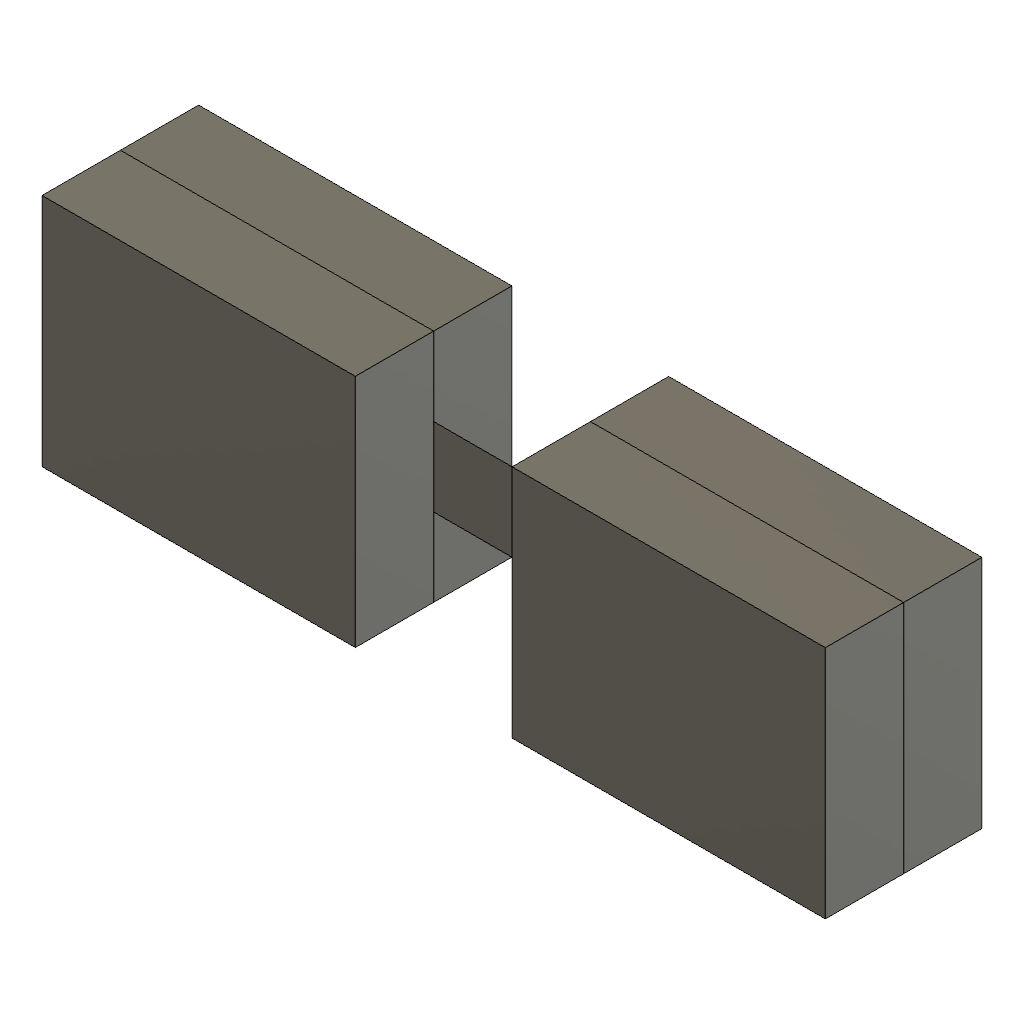
small_sheet_face_extend (Autodesk Fusion 360 design; units mm, degrees)
part number: 2026-10-21-16-23-59-782
Autodesk Fusion 360 part; units mm, degrees
sketch "OwnedMultiSplitBlockSketch_0_small_sheet_face_extend" plane through (0, 0, 0) normal (0, 0, 1) x (1, 0, 0)
  line L0 (0, 0) -> (40, 0)
  line L1 (40, 0) -> (40, 30)
  line L2 (40, 30) -> (0, 30)
  line L3 (0, 30) -> (0, 0)
extrude "OwnedMultiSplitBlockExtrude_0_small_sheet_face_extend" add sketch "OwnedMultiSplitBlockSketch_0_small_sheet_face_extend" along normal blind 20 makes body 1
sketch "OwnedMultiSplitBlockSketch_1_small_sheet_face_extend" plane through (0, 0, 0) normal (0, 0, 1) x (1, 0, 0)
  line L0 (60, 0) -> (100, 0)
  line L1 (100, 0) -> (100, 30)
  line L2 (100, 30) -> (60, 30)
  line L3 (60, 30) -> (60, 0)
extrude "OwnedMultiSplitBlockExtrude_1_small_sheet_face_extend" add sketch "OwnedMultiSplitBlockSketch_1_small_sheet_face_extend" along normal blind 20 separate body makes body 2
ref_plane "WorkPlane1" through (0, 0, 10) normal (0, 0, 1) x (1, 0, 0)
sketch "OwnedSplitPatchBoundary_small_sheet_face_extend" plane through (0, 0, 10) normal (0, 0, 1) x (1, 0, 0)
  line L0 (10, 10) -> (90, 10)
  line L1 (90, 10) -> (90, 20)
  line L2 (90, 20) -> (10, 20)
  line L3 (10, 20) -> (10, 10)
surface "OwnedSplitToolPatch_small_sheet_face_extend" add patch profiles "OwnedSplitPatchBoundary_small_sheet_face_extend" section 1 separate body makes body 3
split "OwnedSplitBodyMultiSheet_small_sheet_face_extend" by plane through (0, 0, 10) normal (0, 0, 1) bodies 1 2 makes body 5 at (73.3333, 20, 20) makes body 4 at (13.3333, 20, 20)
named bodies: "OwnedMultiSplitBlock_0_small_sheet_face_extend", "OwnedMultiSplitBlock_1_small_sheet_face_extend", "OwnedSplitToolSheet_small_sheet_face_extend", "OwnedMultiSplitBlock_0_small_sheet_face_extend (1)", "OwnedMultiSplitBlock_1_small_sheet_face_extend (1)"
